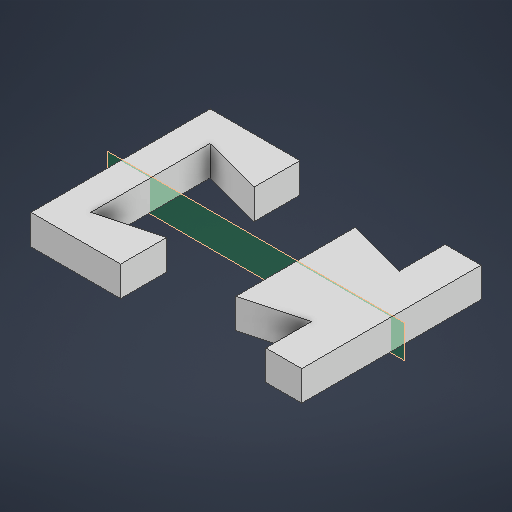
# Autodesk Inventor part: prueba_enganche
Saved by Autodesk Inventor 2027 (Build 310192060, 192F)
## iProperties
Created: 2026-10-13
Part Number: prueba_enganche
Material: Generic
Document SubType Name: Modeling
Designer: Pablo
Density: 1 g/cm^3
Appearance: Default
Author: Pablo
Autodesk Inventor part; units mm, degrees
ref_plane "YZ Plane" through (0, 0, 0) normal (1, 0, 0) x (0, 1, 0)
ref_plane "XZ Plane" through (0, 0, 0) normal (0, 1, 0) x (-1, 0, 0)
ref_plane "XY Plane" through (0, 0, 0) normal (0, 0, 1) x (1, 0, 0)
sketch "Sketch1" plane through (0, 0, 0) normal (0, 1, 0) x (-1, 0, 0)
  line L0 (0, 15) -> (15, 15)
  line L1 (15, 15) -> (15, 0)
  line L2 (0, 0) -> (38.8397, 0)
  line L3 (0, 15) -> (0, 7.3205)
  line L4 (0, 7.3205) -> (10, 10)
  line L5 (10, 10) -> (10, 0)
  line L6 (10, 0) -> (15, 0)
  line L7 (-14.2978, 0) -> (-14.2978, 10)
  line L8 (-14.2978, 10) -> (-24.2978, 7.3205)
  line L9 (-24.2978, 0) -> (-14.2978, 0)
  line L10 (-24.2978, 7.3205) -> (-24.2978, 15)
  line L11 (-24.2978, 15) -> (-30.2978, 15)
  line L12 (-30.2978, 15) -> (-30.2978, 0)
  line L13 (-30.2978, 0) -> (-24.2978, 0)
  point P0 (15, 0)
  dimension "d0" = 30
  dimension "d1" = 20
  dimension "d2" = 75
  dimension "d3" = 10
  dimension "d4" = 15
  dimension "d7" = 20
  dimension "d10" = 75
  dimension "d11" = 6
  dimension "d12" = 10
  constraints: 28 end point, 6 perpendicular, 4 point on line, 3 vertical, 2 collinear, 2 horizontal
  measures "d0" diameter of L0 L2
  measures "d1" diameter of L4.end L2
  measures "d2" angle of L3 L4
  measures "d3" distance between parallel lines of L3 L5
  measures "d4" distance between parallel lines of L3 L1
  measures "d7" diameter of L7.end L9
  measures "d10" angle of L10 L8
  measures "d11" distance between parallel lines of L12 L10
  measures "d12" distance between parallel lines of L7 L10
extrude "Extrusion1" add sketch "Sketch1" along normal blind 5
mirror "Mirror1" about plane through (0, 0, 0) normal (0, 0, 1) of "Extrusion1"
ref_plane "Work Plane1" through (0, 0, 0) normal (0, 0, 1) x (1, 0, 0)
equation "\"d7\" = d1"
equation "\"d10\" = d2"
equation "\"d12\" = d3"
body "Solid1"
